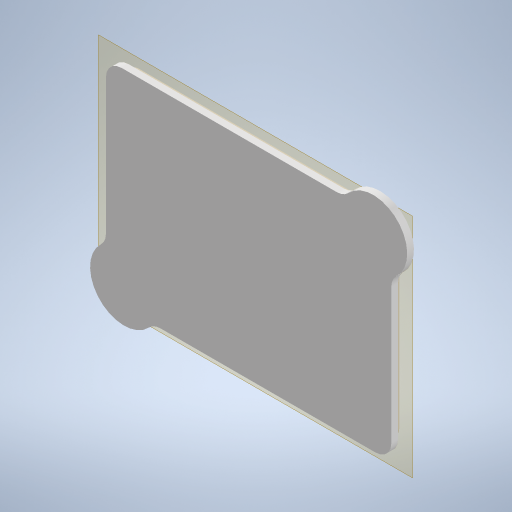
# Autodesk Inventor part: víko součásti
Saved by Autodesk Inventor 2024 (Build 280153000, 153)
## iProperties
Created: 2025-10-14
Part Number: víko součásti
Material: Všeobecné
Document SubType Name: Modeling
Designer: zak
Density: 1 g/cm^3
Appearance: Výchozí
Author: zak
Autodesk Inventor part; units mm, degrees
ref_plane "YZ Plane" through (0, 0, 0) normal (1, 0, 0) x (0, 1, 0)
ref_plane "XZ Plane" through (0, 0, 0) normal (0, 1, 0) x (-1, 0, 0)
ref_plane "XY Plane" through (0, 0, 0) normal (0, 0, 1) x (1, 0, 0)
ref_plane "Pracovní rovina1" through (0, 0, 0) normal (0, 0, 1) x (1, 0, 0)
sketch "Náčrt1" plane through (0, 0, 0) normal (0, 0, 1) x (1, 0, 0)
  line L0 (55, 45.5) -> (-55, 45.5) projected
  line L1 (-63, 37.5) -> (-63, -37.5) projected
  arc A0 (-55, 45.5) -> (-63, 37.5) centre (-55, 37.5) ccw projected
  arc A1 (63, 37.5) -> (55, 45.5) centre (55, 37.5) ccw projected
  line L2 (63, -37.5) -> (63, 37.5) projected
  arc A2 (55, -45.5) -> (63, -37.5) centre (55, -37.5) ccw projected
  line L3 (-55, -45.5) -> (55, -45.5) projected
  arc A3 (-63, -37.5) -> (-55, -45.5) centre (-55, -37.5) ccw projected
  line L4 (63, 21.4065) -> (63, -38.5)
  arc A4 (-56, 45.5) -> (-63, 38.5) centre (-56, 38.5) ccw
  arc A5 (56, -45.5) -> (63, -38.5) centre (56, -38.5) ccw
  arc A6 (65.2273, 26.5272) -> (44.0272, 47.7273) centre (55, 37.5) ccw
  arc A7 (-65.2273, -26.5272) -> (-44.0272, -47.7273) centre (-55, -37.5) ccw
  line L5 (-63, -21.4065) -> (-63, 38.5)
  line L6 (56, -45.5) -> (-38.9065, -45.5)
  line L7 (-56, 45.5) -> (38.9065, 45.5)
  arc A8 (-65.2273, -26.5272) -> (-63, -21.4065) centre (-70, -21.4065) ccw
  arc A9 (-38.9065, -45.5) -> (-44.0272, -47.7273) centre (-38.9065, -52.5) ccw
  arc A10 (65.2273, 26.5272) -> (63, 21.4065) centre (70, 21.4065) ccw
  arc A11 (38.9065, 45.5) -> (44.0272, 47.7273) centre (38.9065, 52.5) ccw
  point P0 (0, 0)
  point P1 (63, 24.8114)
  point P2 (-42.3114, -45.5)
  point P3 (-63, -24.8114)
  point P4 (42.3114, 45.5)
  dimension "d3" = 7
  dimension "d4" = 7
  dimension "d5" = 30
  dimension "d6" = 30
  dimension "d7" = 7
  constraints: 23 point on circle, 12 tangent, 8 centre point, 8 end point, 6 point on line, 4 collinear, 3 equal radius, 2 coincident, 2 parallel, 1 horizontal, 1 perpendicular
  measures "d3" radius of A4
  measures "d4" radius of A5
  measures "d5" diameter of A6
  measures "d6" diameter of A7
  measures "d7" radius of A8
extrude "Vysunutí2" add sketch "Náčrt1" along normal blind 3
sketch "Náčrt2" plane through (0, 0, 0) normal (0, 0, -1) x (-1, 0, 0)
  line L0 (48.0718, 43.5) -> (-48.0718, 43.5) projected
  arc A0 (61, 37.5) -> (55, 43.5) centre (55, 37.5) ccw projected
  line L1 (61, 30.5718) -> (61, 37.5) projected
  line L2 (61, -30.5718) -> (61, 30.5718) projected
  line L3 (55, 43.5) -> (48.0718, 43.5) projected
  line L4 (-48.0718, 43.5) -> (-55, 43.5) projected
  arc A1 (-55, 43.5) -> (-61, 37.5) centre (-55, 37.5) ccw projected
  line L5 (-61, 30.5718) -> (-61, -30.5718) projected
  line L6 (-61, 37.5) -> (-61, 30.5718) projected
  line L7 (-61, -30.5718) -> (-61, -37.5) projected
  arc A2 (-61, -37.5) -> (-55, -43.5) centre (-55, -37.5) ccw projected
  line L8 (-55, -43.5) -> (-48.0718, -43.5) projected
  line L9 (-48.0718, -43.5) -> (48.0718, -43.5) projected
  line L10 (48.0718, -43.5) -> (55, -43.5) projected
  arc A3 (55, -43.5) -> (61, -37.5) centre (55, -37.5) ccw projected
  line L11 (61, -37.5) -> (61, -30.5718) projected
  line L12 (-59, -30.5718) -> (-59, 30.5718)
  line L13 (-59, 30.5718) -> (-59, 37.5)
  arc A4 (-55, 41.5) -> (-59, 37.5) centre (-55, 37.5) ccw
  line L14 (-55, 41.5) -> (-48.0718, 41.5)
  line L15 (-48.0718, 41.5) -> (48.0718, 41.5)
  line L16 (48.0718, 41.5) -> (55, 41.5)
  arc A5 (59, 37.5) -> (55, 41.5) centre (55, 37.5) ccw
  line L17 (59, 37.5) -> (59, 30.5718)
  line L18 (59, 30.5718) -> (59, -30.5718)
  line L19 (59, -30.5718) -> (59, -37.5)
  arc A6 (55, -41.5) -> (59, -37.5) centre (55, -37.5) ccw
  line L20 (55, -41.5) -> (48.0718, -41.5)
  line L21 (48.0718, -41.5) -> (-48.0718, -41.5)
  line L22 (-48.0718, -41.5) -> (-55, -41.5)
  arc A7 (-59, -37.5) -> (-55, -41.5) centre (-55, -37.5) ccw
  line L23 (-59, -37.5) -> (-59, -30.5718)
  point P0 (0, 0)
  dimension "d10" = 2
  constraints: 24 end point, 8 point on circle, 4 centre point, 15 other
  measures "d10" distance between parallel lines of L5 L12
extrude "Vysunutí3" add sketch "Náčrt2" along normal blind 1.5 contours L12 L13 A4 L14 L15 L16 A5 L17 L18 L19 A6 L20 L21 L22 A7 L23
sketch "Náčrt3" plane through (0, 0, -1.5) normal (0, 0, -1) x (-1, 0, 0)
  line L0 (55, 41.5) -> (-55, 41.5) projected
  line L1 (-59, 37.5) -> (-59, -37.5) projected
  arc A0 (-55, 41.5) -> (-59, 37.5) centre (-55, 37.5) ccw projected
  line L2 (59, -37.5) -> (59, 37.5) projected
  line L3 (-55, -41.5) -> (55, -41.5) projected
  arc A1 (-59, -37.5) -> (-55, -41.5) centre (-55, -37.5) ccw projected
  arc A2 (55, -41.5) -> (59, -37.5) centre (55, -37.5) ccw projected
  arc A3 (59, 37.5) -> (55, 41.5) centre (55, 37.5) ccw projected
  line L4 (-55, 42.5) -> (55, 42.5)
  arc A4 (60, 37.5) -> (55, 42.5) centre (55, 37.5) ccw
  line L5 (60, 37.5) -> (60, -37.5)
  arc A5 (55, -42.5) -> (60, -37.5) centre (55, -37.5) ccw
  line L6 (55, -42.5) -> (-55, -42.5)
  arc A6 (-60, -37.5) -> (-55, -42.5) centre (-55, -37.5) ccw
  line L7 (-60, -37.5) -> (-60, 37.5)
  arc A7 (-55, 42.5) -> (-60, 37.5) centre (-55, 37.5) ccw
  point P0 (0, 0)
  dimension "d13" = 1
  constraints: 8 end point, 8 point on circle, 4 centre point, 7 other
  measures "d13" distance between parallel lines of L0 L4
extrude "Vysunutí4" add sketch "Náčrt3" along normal blind 2 contours A3 L2 A2 L3 A1 L1 A0 L0 | L4 A4 L5 A5 L6 A6 L7 A7
